810000_P01_INTERIOR_CAD (Autodesk Fusion 360 design; units mm, degrees)
description: INTERIOR | Nội thất | HS | P01
part number: 810000
description: INTERIOR - WORK WALL LEDGE ASSY | Bàn tựa vách làm việc (cụm) | HS | P01
part number: 810101
description: INTERIOR - LIGHT SHELF ASSY | Kệ đèn hắt (cụm) | HS | P01
part number: 810201
description: INTERIOR - LIGHT SHELF - BACK | Kệ đèn - vách sau | MP | P01
part number: 811201
description: INTERIOR - LIGHT SHELF - SIDE LH | Kệ đèn - vách trái | MP | P01
part number: 811202
description: INTERIOR - LIGHT SHELF - SIDE RH | Kệ đèn - vách phải | MP | P01
part number: 811203
description: ELECTRICAL - LED PROFILE - LIGHT SHELF - SURFACE 23 X 12.5 | Điện - thanh nhôm LED nổi 23 x 12.5 - kệ đèn | HOLD | P01
part number: 718101
description: INTERIOR - LEDGE - TOP | Mặt bàn tựa nhôm gấp 1.5 | MP | P01
part number: 811101
description: INTERIOR - LEDGE BRACKET - HOLD | Ke đỡ bàn tựa (chờ) | HOLD | P01
part number: 818101
description: INTERIOR - SCREEN RAIL - HOLD | Thanh treo màn hình (chờ) | HOLD | P01
part number: 818102
Autodesk Fusion 360 part; units mm, degrees
sketch "SECTION - LIGHT SHELF BACK" plane through (0, 0, 0) normal (1, 0, 0) x (0, 0, -1) in component "811201 INTERIOR - LIGHT SHELF - BACK"
  line L0 (-2230, 766) -> (-2230, 706)
  line L1 (-2230, 706) -> (-2250, 706)
  line L2 (-2250, 706) -> (-2250, 707)
  line L3 (-2250, 707) -> (-2231, 707)
  line L4 (-2231, 707) -> (-2231, 765)
  line L5 (-2231, 765) -> (-2270, 765)
  line L6 (-2270, 765) -> (-2270, 766)
  line L7 (-2270, 766) -> (-2230, 766)
  dimension "d965" = 2230
  dimension "d966" = 2250
  dimension "d967" = 2231
  dimension "d968" = 2270
  dimension "d969" = 706
  dimension "d970" = 707
  dimension "d971" = 765
  dimension "d972" = 766
  constraint vertical L0
  constraint vertical L2
  constraint vertical L4
  constraint vertical L6
  constraint horizontal L1
  constraint horizontal L3
  constraint horizontal L5
  constraint horizontal L7
  measures "d965" horizontal distance of origin L0.start
  measures "d966" horizontal distance of origin L1.end
  measures "d967" horizontal distance of origin L3.end
  measures "d968" horizontal distance of origin L5.end
  measures "d969" vertical distance of origin L0.end
  measures "d970" vertical distance of origin L2.end
  measures "d971" vertical distance of origin L4.end
  measures "d972" vertical distance of origin L6.end
extrude "EXTRUDE - LIGHT SHELF BACK" add sketch "SECTION - LIGHT SHELF BACK" along normal blind 2332 from surface at -1166 makes body 1 in component "811201 INTERIOR - LIGHT SHELF - BACK"
fillet "BEND INSIDE R (sh_r) - LIGHT SHELF BACK" radius 1 2 edges at (0, 765, 2231) (0, 707, 2231) on bodies 1 in component "811201 INTERIOR - LIGHT SHELF - BACK"
fillet "BEND OUTSIDE R (sh_r + sh_t) - LIGHT SHELF BACK" radius 2 2 edges at (0, 766, 2230) (0, 706, 2230) on bodies 1 in component "811201 INTERIOR - LIGHT SHELF - BACK"
sketch "SECTION - LIGHT SHELF LH" plane through (0, 0, 0) normal (0, 1, 0) x (1, 0, 0) in component "811202 INTERIOR - LIGHT SHELF - SIDE LH"
  line L0 (-1166, -2230) -> (-1106, -2230)
  line L1 (-1106, -2230) -> (-1106, -2250)
  line L2 (-1106, -2250) -> (-1107, -2250)
  line L3 (-1107, -2250) -> (-1107, -2231)
  line L4 (-1107, -2231) -> (-1165, -2231)
  line L5 (-1165, -2231) -> (-1165, -2270)
  line L6 (-1165, -2270) -> (-1166, -2270)
  line L7 (-1166, -2270) -> (-1166, -2230)
  dimension "d980" = 1106
  dimension "d981" = 1107
  dimension "d982" = 1165
  dimension "d983" = 1166
  dimension "d984" = 2230
  dimension "d985" = 2250
  dimension "d986" = 2231
  dimension "d987" = 2270
  constraint vertical L1
  constraint vertical L3
  constraint vertical L5
  constraint vertical L7
  constraint horizontal L0
  constraint horizontal L2
  constraint horizontal L4
  constraint horizontal L6
  measures "d980" horizontal distance of origin L0.end
  measures "d981" horizontal distance of origin L2.end
  measures "d982" horizontal distance of origin L4.end
  measures "d983" horizontal distance of origin L6.end
  measures "d984" vertical distance of origin L0.start
  measures "d985" vertical distance of origin L1.end
  measures "d986" vertical distance of origin L3.end
  measures "d987" vertical distance of origin L5.end
extrude "EXTRUDE - LIGHT SHELF LH" add sketch "SECTION - LIGHT SHELF LH" along normal blind 991 from surface at -285 separate body makes body 2 in component "811202 INTERIOR - LIGHT SHELF - SIDE LH"
fillet "BEND INSIDE R (sh_r) - LIGHT SHELF LH" radius 1 2 edges at (-1165, 210.5, 2231) (-1107, 210.5, 2231) on bodies 2 in component "811202 INTERIOR - LIGHT SHELF - SIDE LH"
fillet "BEND OUTSIDE R (sh_r + sh_t) - LIGHT SHELF LH" radius 2 2 edges at (-1166, 210.5, 2230) (-1106, 210.5, 2230) on bodies 2 in component "811202 INTERIOR - LIGHT SHELF - SIDE LH"
sketch "SECTION - LIGHT SHELF RH" plane through (0, 0, 0) normal (0, 1, 0) x (1, 0, 0) in component "811203 INTERIOR - LIGHT SHELF - SIDE RH"
  line L0 (1166, -2230) -> (1106, -2230)
  line L1 (1106, -2230) -> (1106, -2250)
  line L2 (1106, -2250) -> (1107, -2250)
  line L3 (1107, -2250) -> (1107, -2231)
  line L4 (1107, -2231) -> (1165, -2231)
  line L5 (1165, -2231) -> (1165, -2270)
  line L6 (1165, -2270) -> (1166, -2270)
  line L7 (1166, -2270) -> (1166, -2230)
  dimension "d995" = 1106
  dimension "d996" = 1107
  dimension "d997" = 1165
  dimension "d998" = 1166
  dimension "d999" = 2230
  dimension "d1000" = 2250
  dimension "d1001" = 2231
  dimension "d1002" = 2270
  constraint vertical L1
  constraint vertical L3
  constraint vertical L5
  constraint vertical L7
  constraint horizontal L0
  constraint horizontal L2
  constraint horizontal L4
  constraint horizontal L6
  measures "d995" horizontal distance of origin L0.end
  measures "d996" horizontal distance of origin L2.end
  measures "d997" horizontal distance of origin L4.end
  measures "d998" horizontal distance of origin L6.end
  measures "d999" vertical distance of origin L0.start
  measures "d1000" vertical distance of origin L1.end
  measures "d1001" vertical distance of origin L3.end
  measures "d1002" vertical distance of origin L5.end
extrude "EXTRUDE - LIGHT SHELF RH" add sketch "SECTION - LIGHT SHELF RH" along normal blind 991 from surface at -285 separate body makes body 3 in component "811203 INTERIOR - LIGHT SHELF - SIDE RH"
fillet "BEND INSIDE R (sh_r) - LIGHT SHELF RH" radius 1 2 edges at (1165, 210.5, 2231) (1107, 210.5, 2231) on bodies 3 in component "811203 INTERIOR - LIGHT SHELF - SIDE RH"
fillet "BEND OUTSIDE R (sh_r + sh_t) - LIGHT SHELF RH" radius 2 2 edges at (1166, 210.5, 2230) (1106, 210.5, 2230) on bodies 3 in component "811203 INTERIOR - LIGHT SHELF - SIDE RH"
ref_plane "WorkPlane1" through (0, 0, 2217.5) normal (0, 0, 1) x (1, 0, 0) in component "718101 ELECTRICAL - LED PROFILE - LIGHT SHELF - SURFACE 23 X 12.5"
sketch "OUTLINE - LED PROFILE RH" plane through (0, 0, 2217.5) normal (0, 0, 1) x (1, 0, 0) in component "718101 ELECTRICAL - LED PROFILE - LIGHT SHELF - SURFACE 23 X 12.5"
  line L0 (1128, -285) -> (1151, -285)
  line L1 (1151, -285) -> (1151, 706)
  line L2 (1151, 706) -> (1128, 706)
  line L3 (1128, 706) -> (1128, -285)
  dimension "d1012" = 23
  dimension "d1013" = 991
  dimension "d1014" = 1128
  dimension "d1015" = 285
  constraint horizontal L0
  constraint vertical L1
  constraint horizontal L2
  constraint vertical L3
  measures "d1012" horizontal distance of L0.start L0.end
  measures "d1013" vertical distance of L0.start L2.end
  measures "d1014" horizontal distance of origin L0.start
  measures "d1015" vertical distance of origin L0.start
extrude "EXTRUDE - LED PROFILE RH" add sketch "OUTLINE - LED PROFILE RH" along normal blind 12.5 separate body makes body 4 in component "718101 ELECTRICAL - LED PROFILE - LIGHT SHELF - SURFACE 23 X 12.5"
sketch "SECTION - LEDGE TOP" plane through (0, 0, 0) normal (0, 1, 0) x (1, 0, 0) in component "811101 INTERIOR - LEDGE - TOP"
  line L0 (911, -1067) -> (1161, -1067)
  line L1 (1161, -1067) -> (1161, -1042)
  line L2 (1161, -1042) -> (1159.5, -1042)
  line L3 (1159.5, -1042) -> (1159.5, -1065.5)
  line L4 (1159.5, -1065.5) -> (912.5, -1065.5)
  line L5 (912.5, -1065.5) -> (912.5, -1042)
  line L6 (912.5, -1042) -> (911, -1042)
  line L7 (911, -1042) -> (911, -1067)
  dimension "d1018" = 1161
  dimension "d1019" = 1159.5
  dimension "d1020" = 912.5
  dimension "d1021" = 911
  dimension "d1022" = 1067
  dimension "d1023" = 1042
  dimension "d1024" = 1065.5
  dimension "d1025" = 1042
  constraint vertical L1
  constraint vertical L3
  constraint vertical L5
  constraint vertical L7
  constraint horizontal L0
  constraint horizontal L2
  constraint horizontal L4
  constraint horizontal L6
  measures "d1018" horizontal distance of origin L0.end
  measures "d1019" horizontal distance of origin L2.end
  measures "d1020" horizontal distance of origin L4.end
  measures "d1021" horizontal distance of origin L6.end
  measures "d1022" vertical distance of origin L0.start
  measures "d1023" vertical distance of origin L1.end
  measures "d1024" vertical distance of origin L3.end
  measures "d1025" vertical distance of origin L5.end
extrude "EXTRUDE - LEDGE TOP" add sketch "SECTION - LEDGE TOP" along normal blind 1000 from surface at -259.5 separate body makes body 5 in component "811101 INTERIOR - LEDGE - TOP"
fillet "BEND INSIDE R (lg_r) - LEDGE TOP" radius 1.5 2 edges at (912.5, 240.5, 1065.5) (1159.5, 240.5, 1065.5) on bodies 5 in component "811101 INTERIOR - LEDGE - TOP"
fillet "BEND OUTSIDE R (lg_r + lg_t) - LEDGE TOP" radius 3 2 edges at (911, 240.5, 1067) (1161, 240.5, 1067) on bodies 5 in component "811101 INTERIOR - LEDGE - TOP"
sketch "SECTION - LEDGE BRACKET 1" plane through (0, 0, 0) normal (0, 1, 0) x (1, 0, 0) in component "818101 INTERIOR - LEDGE BRACKET - HOLD"
  line L0 (961, -915.5) -> (1159.5, -915.5)
  line L1 (1159.5, -915.5) -> (1159.5, -1062.5)
  line L2 (1159.5, -1062.5) -> (1156.5, -1065.5)
  line L3 (1156.5, -1065.5) -> (961, -1065.5)
  line L4 (961, -1065.5) -> (961, -915.5)
  dimension "d1033" = 1159.5
  dimension "d1034" = 1156.5
  dimension "d1035" = 961
  dimension "d1036" = 915.5
  dimension "d1037" = 1062.5
  dimension "d1038" = 1065.5
  constraint vertical L1
  constraint vertical L4
  constraint horizontal L0
  constraint horizontal L3
  measures "d1033" horizontal distance of origin L0.end
  measures "d1034" horizontal distance of origin L2.end
  measures "d1035" horizontal distance of origin L3.end
  measures "d1036" vertical distance of origin L0.start
  measures "d1037" vertical distance of origin L1.end
  measures "d1038" vertical distance of origin L2.end
extrude "EXTRUDE - LEDGE BRACKET 1" add sketch "SECTION - LEDGE BRACKET 1" along normal blind 30 from surface at 83.63 separate body makes body 6 in component "818101 INTERIOR - LEDGE BRACKET - HOLD"
sketch "SECTION - LEDGE BRACKET 2" plane through (0, 0, 0) normal (0, 1, 0) x (1, 0, 0) in component "818101 INTERIOR - LEDGE BRACKET - HOLD"
  line L0 (961, -915.5) -> (1159.5, -915.5)
  line L1 (1159.5, -915.5) -> (1159.5, -1062.5)
  line L2 (1159.5, -1062.5) -> (1156.5, -1065.5)
  line L3 (1156.5, -1065.5) -> (961, -1065.5)
  line L4 (961, -1065.5) -> (961, -915.5)
  dimension "d1042" = 1159.5
  dimension "d1043" = 1156.5
  dimension "d1044" = 961
  dimension "d1045" = 915.5
  dimension "d1046" = 1062.5
  dimension "d1047" = 1065.5
  constraint vertical L1
  constraint vertical L4
  constraint horizontal L0
  constraint horizontal L3
  measures "d1042" horizontal distance of origin L0.end
  measures "d1043" horizontal distance of origin L2.end
  measures "d1044" horizontal distance of origin L3.end
  measures "d1045" vertical distance of origin L0.start
  measures "d1046" vertical distance of origin L1.end
  measures "d1047" vertical distance of origin L2.end
extrude "EXTRUDE - LEDGE BRACKET 2" add sketch "SECTION - LEDGE BRACKET 2" along normal blind 30 from surface at 449.32 separate body makes body 7 in component "818101 INTERIOR - LEDGE BRACKET - HOLD"
ref_plane "WorkPlane1" through (0, 0, 1275) normal (0, 0, 1) x (1, 0, 0) in component "818102 INTERIOR - SCREEN RAIL - HOLD"
sketch "OUTLINE - SCREEN RAIL" plane through (0, 0, 1275) normal (0, 0, 1) x (1, 0, 0) in component "818102 INTERIOR - SCREEN RAIL - HOLD"
  line L0 (1136, -209.5) -> (1161, -209.5)
  line L1 (1161, -209.5) -> (1161, 690.5)
  line L2 (1161, 690.5) -> (1136, 690.5)
  line L3 (1136, 690.5) -> (1136, -209.5)
  dimension "d1053" = 25
  dimension "d1054" = 900
  dimension "d1055" = 1136
  dimension "d1056" = 209.5
  constraint horizontal L0
  constraint vertical L1
  constraint horizontal L2
  constraint vertical L3
  measures "d1053" horizontal distance of L0.start L0.end
  measures "d1054" vertical distance of L0.start L2.end
  measures "d1055" horizontal distance of origin L0.start
  measures "d1056" vertical distance of origin L0.start
extrude "EXTRUDE - SCREEN RAIL" add sketch "OUTLINE - SCREEN RAIL" along normal blind 50 separate body makes body 8 in component "818102 INTERIOR - SCREEN RAIL - HOLD"
ref_plane "WorkPlane1" through (0, 766, 0) normal (0, 1, 0) x (0, 0, 1) in component "811201 INTERIOR - LIGHT SHELF - BACK"
sketch "HOLE - LIGHT SHELF BACK CABLE HOLE 1" plane through (0, 766, 0) normal (0, 1, 0) x (1, 0, 0) in component "811201 INTERIOR - LIGHT SHELF - BACK"
  circle A0 centre (355, -2250) radius 5
  dimension "d1061" = 10
  dimension "d1062" = 355
  dimension "d1063" = 2250
  measures "d1061" diameter of A0
  measures "d1062" horizontal distance of origin A0.centre
  measures "d1063" vertical distance of origin A0.centre
extrude "CUT - LIGHT SHELF BACK CABLE HOLE 1" cut sketch "HOLE - LIGHT SHELF BACK CABLE HOLE 1" against normal blind 2 bodies 1 in component "811201 INTERIOR - LIGHT SHELF - BACK"
ref_plane "WorkPlane1" through (1166, 0, 0) normal (1, 0, 0) x (0, 1, 0) in component "811203 INTERIOR - LIGHT SHELF - SIDE RH"
sketch "HOLE - LIGHT SHELF RH CABLE HOLE 2" plane through (1166, 0, 0) normal (1, 0, 0) x (0, 0, -1) in component "811203 INTERIOR - LIGHT SHELF - SIDE RH"
  circle A0 centre (-2250, -209.5) radius 5
  dimension "d1068" = 10
  dimension "d1069" = 209.5
  dimension "d1070" = 2250
  measures "d1068" diameter of A0
  measures "d1069" vertical distance of origin A0.centre
  measures "d1070" horizontal distance of origin A0.centre
extrude "CUT - LIGHT SHELF RH CABLE HOLE 2" cut sketch "HOLE - LIGHT SHELF RH CABLE HOLE 2" against normal blind 2 bodies 3 in component "811203 INTERIOR - LIGHT SHELF - SIDE RH"
component "810101 INTERIOR - WORK WALL LEDGE ASSY" placed x (1, 0, 0) y (0, 1, 0) z (0, 0, 1) at (0, 0, 0)
component "810201 INTERIOR - LIGHT SHELF ASSY" placed x (1, 0, 0) y (0, 1, 0) z (0, 0, 1) at (0, 0, 0)
component "818102 INTERIOR - SCREEN RAIL - HOLD" placed x (1, 0, 0) y (0, 1, 0) z (0, 0, 1) at (0, 0, 0)
component "811101 INTERIOR - LEDGE - TOP" placed x (1, 0, 0) y (0, 1, 0) z (0, 0, 1) at (0, 0, 0) in component "810101 INTERIOR - WORK WALL LEDGE ASSY"
component "818101 INTERIOR - LEDGE BRACKET - HOLD" placed x (1, 0, 0) y (0, 1, 0) z (0, 0, 1) at (0, 0, 0) in component "810101 INTERIOR - WORK WALL LEDGE ASSY"
component "811201 INTERIOR - LIGHT SHELF - BACK" placed x (1, 0, 0) y (0, 1, 0) z (0, 0, 1) at (0, 0, 0) in component "810201 INTERIOR - LIGHT SHELF ASSY"
component "811202 INTERIOR - LIGHT SHELF - SIDE LH" placed x (1, 0, 0) y (0, 1, 0) z (0, 0, 1) at (0, 0, 0) in component "810201 INTERIOR - LIGHT SHELF ASSY"
component "811203 INTERIOR - LIGHT SHELF - SIDE RH" placed x (1, 0, 0) y (0, 1, 0) z (0, 0, 1) at (0, 0, 0) in component "810201 INTERIOR - LIGHT SHELF ASSY"
component "718101 ELECTRICAL - LED PROFILE - LIGHT SHELF - SURFACE 23 X 12.5" placed x (1, 0, 0) y (0, 1, 0) z (0, 0, 1) at (0, 0, 0) in component "810201 INTERIOR - LIGHT SHELF ASSY"
equation "pod_w = 2500 mm" comment "DECIDED: skeleton P04: D-01; conventions s4 (X = +-1250)"
equation "pod_d = 1700 mm" comment "DECIDED: skeleton P04: D-01; conventions s4 (Y = +-850)"
equation "pod_h = 2400 mm" comment "DECIDED: skeleton P04: D-21 (room floor to roof skin top)"
equation "glide_h = 10 mm" comment "ASSUMPTION: skeleton P04: layout study inputs.py glide_h"
equation "band_h = 100 mm" comment "SOURCE: skeleton P04: layout study B1 list B-BAND 100x40; inputs.py base_h"
equation "band_t = 40 mm" comment "SOURCE: skeleton P04: layout study B1 list B-BAND 100x40"
equation "skin_t = 3 mm" comment "DECIDED: skeleton P04: ACP skin, walls and ceiling (D-16; PM ruling 2026-10-31 on outer_t)"
equation "bond_t = 3 mm" comment "DECIDED: skeleton P04: bond line between the ACP and the frame (PM ruling 2026-10-31 on outer_t)"
equation "frame_t = 40 mm" comment "DECIDED: skeleton P04: aluminium frame tube depth, walls and ceiling (PM ruling 2026-10-31 on outer_t)"
equation "outer_t = skin_t + bond_t + frame_t" comment "DECIDED: skeleton P04: PM ruling 2026-10-31: ACP 3 + bond line 3 + frame 40, walls and ceiling (was 43)"
equation "cav_gap = 4 mm" comment "DECIDED: skeleton P04: D-16, D-42: the gap between the outer panel and the lining cassette in the wall and ceiling stack"
equation "cass_t = 34 mm" comment "SOURCE: skeleton P04: layout study B1 final list L-CASS 34 (tray + 25 gap + felt 9)"
equation "stack_t = outer_t + cav_gap + cass_t" comment "CALCULATION: skeleton P04: D-16, D-42 stack, walls and ceiling: outer panel + cavity gap + cassette (PM ruling 2026-10-31 on outer_t)"
equation "wall_depth = 1495 mm" comment "DECIDED: skeleton P04: PM ruling pass C: side walls start at the decor back plate (Y -645), as v1 (1496)"
equation "lin_gap = 4 mm" comment "ASSUMPTION: skeleton P04: PM ruling pass C: gap above the upper side linings so they stay floating (= the 4 mm stack gap)"
equation "seam_gap = 2.26 mm" comment "DECIDED: skeleton P04: PM ruling 2026-10-31 (Mechanical Checker F-001, F-005): the Joints Engineer's 2.26 mm at all nine site seam types, set by a metal stop (1.5 stop washer + 0.76 rivnut head; joints register section 2.8)"
equation "mat_t = 3 mm" comment "DECIDED: skeleton P04: D-72, PM ruling 2026-10-31 (from BASE): the 3 mm floor mat under the floor ply"
equation "floor_t = 9 mm" comment "DECIDED: skeleton P04: PM ruling 2026-10-31: 9 mm floor panels (was 15, layout study B1 list), on the mat"
equation "thresh_h = 13 mm" comment "DECIDED: skeleton P04: PM ruling 2026-10-31: 13 mm, a US-accessible threshold (D-18 had 20); the kick strip keeps its kick_gap above it"
equation "thresh_d = 60 mm" comment "SOURCE: skeleton P04: layout study B1 list B-THRESH 1176 x 60 x 20"
equation "decor_d = 205 mm" comment "SOURCE: skeleton P04: v1 geometry per the PM ruling on D-39 (as v1; the drawings win): v1 decor-frame drawing frames 191 (left) and 197 (right) deep plus ACP and back plate = the v1 STEP shell, Y -850 to -645 = 205. D-39 and the B1 list say 230-235 (v1 BOM); see BUILD-RECORD-P02"
equation "dl_w = 278 mm" comment "SOURCE: skeleton P04: B1 list F-DL 278 (v1 BOM DL)"
equation "dr_w = 1016 mm" comment "SOURCE: skeleton P04: B1 list F-DR 1016 (v1 STEP solid 78)"
equation "dt_w = 1697 mm" comment "SOURCE: skeleton P04: B1 list F-DT 1697 (v1 BOM DT)"
equation "dt_h = 280 mm" comment "SOURCE: skeleton P04: B1 list F-DT 280"
equation "door_w = 1176 mm" comment "DECIDED: skeleton P04: D-46"
equation "door_h = 2011 mm" comment "SOURCE: skeleton P04: B1 list F-GLASS-DOOR 2011; v1 STEP solid 238"
equation "glass_t = 8.76 mm" comment "DECIDED: skeleton P04: D-46 (4+4 laminate)"
equation "glass_y = 699 mm" comment "SOURCE: skeleton P04: v1 STEP solid 238 centre Y = -699 (layout study data)"
equation "kick_d = 20 mm" comment "ASSUMPTION: skeleton P04: kick strip envelope depth (D-40 gives the height only)"
equation "kick_gap = 7 mm" comment "SOURCE: skeleton P04: FRONT door unit: 7 mm running gap between the threshold and the kick strip for the drop seal (Mechanical Checker F-002 on P03)"
equation "fr_dz = 17 mm" comment "CALCULATION: skeleton P04: v1 front top 2417 (v2 frame) - pod_h 2400"
equation "door_xl = 289 mm" comment "SOURCE: skeleton P04: V1-FRONT-FACETS: door left edge X -961 = -1250 + 289"
equation "door_xbr = 1464 mm" comment "SOURCE: skeleton P04: V1-FRONT-FACETS: door bottom-right X 214"
equation "door_xtr = 1182 mm" comment "SOURCE: skeleton P04: V1-FRONT-FACETS: door top-right X -68"
equation "door_zb = 122 mm - fr_dz" comment "SOURCE: skeleton P04: V1-FRONT-FACETS: door bottom Z 122"
equation "door_zt = 2133 mm - fr_dz" comment "SOURCE: skeleton P04: V1-FRONT-FACETS: door top Z 2133"
equation "glass_gap = 4 mm" comment "DECIDED: skeleton P04: PM ruling 2026-10-31 on Mechanical Checker F-014: the fixed glass's free edge runs parallel to the door's slanted edge, 4.0 mm away (FRONT's glass in PR #28 is the reference)"
equation "fix_xbr = 302 mm" comment "SOURCE: skeleton P04: V1-FRONT-FACETS: fixed glass bottom-right X 948 = 1250 - 302"
equation "fix_xk = 501 mm" comment "SOURCE: skeleton P04: V1-FRONT-FACETS: fixed glass knee X 749 = 1250 - 501"
equation "fix_zk = 1538 mm - fr_dz" comment "SOURCE: skeleton P04: V1-FRONT-FACETS: fixed glass knee Z 1538"
equation "fix_xtr = 1480 mm" comment "SOURCE: skeleton P04: V1-FRONT-FACETS: fixed glass top-right X 230 = -1250 + 1480"
equation "fix_zb = 119 mm - fr_dz" comment "SOURCE: skeleton P04: V1-FRONT-FACETS: fixed glass bottom Z 119"
equation "fix_zt = 2136 mm - fr_dz" comment "SOURCE: skeleton P04: V1-FRONT-FACETS: fixed glass top Z 2136"
equation "dt_zb = 2137 mm - fr_dz" comment "SOURCE: skeleton P04: V1-FRONT-FACETS: DT and DR edge above the glass Z 2137"
equation "ch_zlo = 2217 mm - fr_dz" comment "SOURCE: skeleton P04: V1-FRONT-FACETS: top chamfer front edge Z 2217 at Y -848"
equation "ch_yb = 672 mm" comment "SOURCE: skeleton P04: V1-FRONT-FACETS: top chamfer back edge Y -672"
equation "dl_x2 = 92 mm" comment "SOURCE: skeleton P04: V1-FRONT-FACETS: DL facet knee X -1158 = -1250 + 92"
equation "dl_y2 = 752 mm" comment "SOURCE: skeleton P04: V1-FRONT-FACETS: DL facet knee Y -752"
equation "dl_x3 = 271 mm" comment "SOURCE: skeleton P04: V1-FRONT-FACETS: DL front corner X -979"
equation "dl_y3 = 844 mm" comment "SOURCE: skeleton P04: V1-FRONT-FACETS: DL front corner Y -844"
equation "dl_y1 = 670 mm" comment "SOURCE: skeleton P04: V1-FRONT-FACETS: DL outer facet start Y -670"
equation "dl_zo = 2414 mm - fr_dz" comment "SOURCE: skeleton P04: V1-FRONT-FACETS: DL top at the outer corner Z 2414"
equation "dt_x2 = 281 mm" comment "SOURCE: skeleton P04: V1-FRONT-FACETS: DT lower facet left X -969 = -1250 + 281"
equation "dt_y2 = 767 mm" comment "SOURCE: skeleton P04: V1-FRONT-FACETS: DT lower facet left Y -767"
equation "dt_y3 = 753 mm" comment "SOURCE: skeleton P04: V1-FRONT-FACETS: DT lower facet outer Y -753 at X -1154"
equation "dr_xc = 198 mm" comment "SOURCE: skeleton P04: V1-FRONT-FACETS: DR corner facet front X 1052 = 1250 - 198"
equation "dt_xr = 1699 mm" comment "SOURCE: skeleton P04: V1-FRONT-FACETS: DT/DR joint at the top, X 449 = -1250 + 1699 (PM ruling pass C)"
equation "dr_yc = 672 mm" comment "SOURCE: skeleton P04: V1-FRONT-FACETS: DR corner facet back Y -672"
equation "fix_xbl = door_xbr + ( door_zb - fix_zb ) * ( door_xbr - door_xtr ) / ( door_zt - door_zb ) + glass_gap * sqrt(( door_xbr - door_xtr ) * ( door_xbr - door_xtr ) + ( door_zt - door_zb ) * ( door_zt - door_zb )) / ( door_zt - door_zb )" comment "CALCULATION: skeleton P04: F-014: fixed glass bottom-left, on the line glass_gap from the door's slanted edge (was v1's 1468)"
equation "fix_xtl = door_xbr + ( door_zb - fix_zt ) * ( door_xbr - door_xtr ) / ( door_zt - door_zb ) + glass_gap * sqrt(( door_xbr - door_xtr ) * ( door_xbr - door_xtr ) + ( door_zt - door_zb ) * ( door_zt - door_zb )) / ( door_zt - door_zb )" comment "CALCULATION: skeleton P04: F-014: fixed glass top-left, on the same line (was v1's 1184)"
equation "floor_top = mat_t + floor_t" comment "CALCULATION: skeleton P04: D-72: the floor top, Z 12 (mat 3 + ply 9); the threshold stands thresh_h above the room floor"
equation "wall_z0 = glide_h + band_h" comment "CALCULATION: skeleton P04: base band top: glides + band"
equation "panel_z0 = wall_z0 + seam_gap" comment "CALCULATION: skeleton P04: walls stand one seam_gap above the band top (joints register 2.8, IF-01)"
equation "wall_h = pod_h - wall_z0" comment "CALCULATION: skeleton P04: 2290 = layout study v2_model wall_h"
equation "side_h = ( wall_h - 2 * seam_gap ) / 2" comment "CALCULATION: skeleton P04: D-23: 2 sheets per side wall; the gap on the band and the horizontal seam (joints register 2.8)"
equation "side_l = wall_depth - seam_gap" comment "CALCULATION: skeleton P04: side panel length along Y: the seam_gap at the decor's back plate (joints register 2.8, IF-07)"
equation "back_oh = pod_h - outer_t - seam_gap - panel_z0" comment "CALCULATION: skeleton P04: PM ruling 2026-10-31 (pass D, F-004): the back outer frames run up to the ceiling frame (pod_h - outer_t), less the seam_gap under it, closing the slot at the back top edge"
equation "back_ph = ( back_oh - seam_gap ) / 2" comment "CALCULATION: skeleton P04: D-23: 4 sheets on the back, two equal rows with one seam_gap between them (joints register 2.8); the lower back linings match the lower row, as on the side walls"
equation "half_pw = ( pod_w - 2 * outer_t - 3 * seam_gap ) / 2" comment "CALCULATION: skeleton P04: SKIN width of each back and ceiling panel: two skins and three seam_gap seams between the side frames (F-001, joints register 2.8)"
equation "close_gap = 5.5 mm" comment "DECIDED: skeleton P04: PM ruling 2026-10-31 (joints register, F-011/F-012): frame gap at the closing seams B1-B2, B3-B4 and C1-C2, which have no hard stop (slotted holes, thicker gasket)"
equation "half_fw = ( pod_w - 2 * outer_t - 2 * seam_gap - close_gap ) / 2" comment "CALCULATION: skeleton P04: FRAME width of each back and ceiling panel: the skins overhang their frames by half_pw - half_fw at the closing seam (PM ruling 2026-10-31)"
equation "inner_w = pod_w - 2 * stack_t" comment "CALCULATION: skeleton P04: inside width between the side linings"
equation "bolt_edge_inset = 220 mm" comment "DECIDED: skeleton P04: PM ruling 2026-10-31: on every bolted edge the end bolts sit this far in from each panel end (the FRAME end, where the bolts go), the rest evenly spaced"
equation "spigot_inset = 100 mm" comment "DECIDED: skeleton P04: PM ruling 2026-10-31: locating spigots this far in from each panel end (round hole at one end, slot at the other)"
equation "base_bolt_edge = bolt_edge_inset" comment "DECIDED: skeleton P04: J-BASE-01 wall to band: the edge rule (kept by this name for parts already linked)"
equation "n_base_bolt = 4" comment "DECIDED: skeleton P04: PM ruling 2026-10-31, J-BASE-01: bolts per panel along the band, evenly spaced"
equation "base_spigot_inset = spigot_inset" comment "DECIDED: skeleton P04: J-BASE-01: the spigot rule (kept by this name for parts already linked)"
equation "base_side_y0 = pod_d / 2 - wall_depth + seam_gap" comment "CALCULATION: skeleton P04: J-BASE-01: side bolt lines start at the side panel's front end (first bolt base_bolt_edge further on)"
equation "side_base_pitch = ( side_l - 2 * base_bolt_edge ) / ( n_base_bolt - 1 )" comment "CALCULATION: skeleton P04: J-BASE-01 bolt pitch along a side panel"
equation "base_back_x0 = pod_w / 2 - outer_t - seam_gap" comment "CALCULATION: skeleton P04: J-BASE-01: back bolt lines start at each back FRAME's outer end, X -/+ this (first bolt base_bolt_edge further in)"
equation "back_base_pitch = ( half_fw - 2 * base_bolt_edge ) / ( n_base_bolt - 1 )" comment "DECIDED: skeleton P04: PM ruling 2026-10-31 (Reviewer 5 P2 on #58): J-BASE-01 pitch along a back panel, measured on the FRAME (half_fw), where the bolts go; 'panel end' means the frame end"
equation "ceil_bolt_z = pod_h - outer_t + frame_t / 2" comment "DECIDED: skeleton P04: PM ruling 2026-10-31, J-CEIL-01 wall to ceiling: the bolt line on the ceiling frame's centre (Z 2374)"
equation "n_ceil_side_bolt = 4" comment "DECIDED: skeleton P04: PM ruling 2026-10-31, J-CEIL-01: bolts along each side wall top"
equation "n_ceil_back_bolt = 4" comment "DECIDED: skeleton P04: PM ruling 2026-10-31, J-CEIL-01: bolts along each back panel top, like the base (pitch about 253, every edge 350 or less; joints register: 82 bolts in all)"
equation "ceil_side_y0 = pod_d / 2 - wall_depth" comment "DECIDED: skeleton P04: PM ruling 2026-10-31 (joints register): J-CEIL-01 side bolt lines start at Y -645, measured along the ceiling (first bolt bolt_edge_inset further on)"
equation "ceil_side_pitch = ( wall_depth - 2 * bolt_edge_inset ) / ( n_ceil_side_bolt - 1 )" comment "DECIDED: skeleton P04: PM ruling 2026-10-31 (joints register): J-CEIL-01 pitch along a side wall top, over the ceiling's length (was over the side panel's)"
equation "ceil_back_x0 = pod_w / 2 - outer_t - seam_gap" comment "DECIDED: skeleton P04: PM ruling 2026-10-31 (joints register): J-CEIL-01 back bolt lines start at each back frame's outer end, X -/+ this"
equation "ceil_back_pitch = ( half_fw - 2 * bolt_edge_inset ) / ( n_ceil_back_bolt - 1 )" comment "DECIDED: skeleton P04: PM ruling 2026-10-31 (joints register): J-CEIL-01 pitch along a back panel top, on the frame (half_fw)"
equation "tube_w = 20 mm" comment "CONFIRMED: D-34, D-54: aluminium 20 x 40 x 1.2 members (the 20 mm face lies in the plane of the panel)"
equation "tube_t = 1.2 mm" comment "CONFIRMED: D-54: the frames stay 1.2 mm (rivnut grip check passed); D-85 keeps the ceiling's cross members at 1.2 too, since they carry the overhead clips and catches (T07, T08 test on 1.2)"
equation "back_w = 40 mm" comment "CONFIRMED: R-J3 (joints register 2.4): the ceiling's back member is 40 x 40, so the back panel's top tube overlaps it by 34 and its rivnuts sit on a 40 mm face"
equation "fr_n = 3" comment "CONFIRMED: PM ruling on the CEILING plan, 2026-10-31: 3 cross members between the side and seam members"
equation "fr_pitch = ( wall_depth - tube_w ) / ( fr_n + 1 )" comment "CALCULATION: centre spacing of the cross members, front member to back member: (1495 - 20) / 4 = 368.75, 400 or less (D-16)"
equation "hole_clr = 7 mm" comment "CONFIRMED: R-J6 (joints register 2.9): bolt clearance hole, positioned to +/-0.2 from the spigot hole"
equation "hole_acc = 19 mm" comment "CONFIRMED: joints register 2.2, 2.9: access hole, so the 18 mm head washer goes in with the bolt"
equation "hole_rvn = 9.53 mm" comment "SOURCE: H-03 Sherex CAH2-610-4.2 rivnut (steel, D-131): hole 9.53 +0.10, as the aluminium part's (joints register H-03, SHX)"
equation "spig_hole = 8.5 mm" comment "CONFIRMED: R-J13: spigot hole 8.5, round at one end of the edge, an 8.5 x 14 slot along it at the other"
equation "spig_slot = 14 mm" comment "CONFIRMED: R-J13: the spigot slot's length along the edge (+/-2.75 of travel for the 8 mm spigot)"
equation "lead_in = 1 mm" comment "CONFIRMED: R-J9 (joints register 2.10): 1 x 45 deg lead-in on the lower edges of the C1-C2 faces, so C2 drops past C1 without catching the seal"
equation "cj_back_y = pod_d / 2 - outer_t + frame_t / 2" comment "CONFIRMED: R-J15 (joints register 2.4): the back edges' bolt line on the back panel's top tube centre (Y +824)"
equation "cj_pin_n = 4" comment "CONFIRMED: J-CEIL-02 (joints register 3.6): 4 pins at the 220 mm rule along the C1-C2 seam"
equation "cj_pin_pitch = ( wall_depth - 2 * bolt_edge_inset ) / ( cj_pin_n - 1 )" comment "CALCULATION: J-CEIL-02 pins along the ceiling's 1495 from Y -645 + 220, as the side edges (joints register 2.9)"
equation "cj_spig_x0 = close_gap / 2 + spigot_inset" comment "CALCULATION: R-J13: spigots 100 in from each frame end. The round hole sits at the centre-seam end, since ST-04 runs from the round hole to the closing face (+/-0.1); the slot at the side end lets the side bolts pull C1 and C2 onto their stops"
equation "cj_spig_x1 = close_gap / 2 + half_fw - spigot_inset" comment "CALCULATION: R-J13: the slot 100 in from the frame's side end"
equation "x1_ov = 16 mm" comment "CONFIRMED: PM ruling 2026-11-01 (D-87 hooks): cross member X1 sits this far over the soffit's back edge, so the soffit's back hangers have a member above them; its back face stays over the cassette for the clips"
equation "hang_x = inner_w / 4" comment "CALCULATION: PM ruling 2026-11-01: soffit keyhole studs at the middle of each ceiling half's front member and X1 (clear of the clips, the catches and the roof slot)"
equation "lock_x = inner_w / 2 - 66 mm" comment "ASSUMPTION: PM ruling 2026-11-01: two captive screws (5 mm key) lock the soffit, so taking a cassette out can never free it; both in C1's front member over the soffit's left inlet plenum, where no cartridge is, reached through the left hinged underside (X -1100 and -950)"
equation "lock_dx = 150 mm" comment "ASSUMPTION: spacing of the two soffit lock screws along the front member"
equation "slot_x0 = 872 mm" comment "SOURCE: air report 7e (sized on skeleton P04): roof slot X 872 to 1157, over the soffit's exhaust fan box"
equation "slot_w = 285 mm" comment "SOURCE: air report 7e: roof slot 285 x 294"
equation "slot_d = 294 mm" comment "SOURCE: air report 7e: roof slot 285 x 294"
equation "slot_y0 = -620 mm" comment "CONFIRMED: D-61, PM ruling 2026-10-31: roof slot Y -620 to -326, 5 mm clear of the frame's front member"
equation "cs_front = 360 mm" comment "CONFIRMED: D-60 soffit over the door head, 360 deep and 220 tall (Z 2120 to 2340), flush with the air column's face (PM rulings 2026-10-31, air group); the cassettes stop at its back face (PM ruling 2026-10-31)"
equation "cs_gap = 3 mm" comment "ASSUMPTION: edge gap round the cassette to the next lining, the other cassette or the top decor block; the 3.2 mm PORON gasket (selection D) just touches across it"
equation "cs_w = inner_w / 2 - 2 * cs_gap" comment "CALCULATION: cassette width: half the 2338 inside width less a gap each side = 1163"
equation "cs_d = wall_depth - stack_t - cs_front - 2 * cs_gap" comment "CALCULATION: cassette length front to back: the 1414 envelope (decor back plate to the back lining face) less the soffit and a gap each end = 1408 with no soffit"
equation "tray_t = 0.5 mm" comment "CONFIRMED: D-37: galvanised steel tray 0.5 mm (DX51D+Z, selection B)"
equation "tray_h = cass_t" comment "CALCULATION: PM ruling on the CEILING plan, 2026-10-31: the returns run the full cassette depth (34) and turn in under the felt edge"
equation "lip_w = 12 mm" comment "CONFIRMED: PM ruling on the CEILING plan, 2026-10-31: a 12 mm lip under the felt edge"
equation "bend_r = tray_t" comment "ASSUMPTION: inside bend radius 1 x t for 0.5 mm DX51D (the sheet metal rule's bend radius is its Thickness); the factory's tooling sets it (guideline 9)"
equation "felt_t = 9 mm" comment "CONFIRMED: D-17: 9 mm PET felt on the cassette face (plan VT03-PET)"
equation "felt_c = 1 mm" comment "ASSUMPTION: felt edge clearance inside the returns, so the felt drops onto the lips"
equation "gap_h = tray_h - felt_t - 2 * tray_t" comment "CALCULATION: air gap between the tray base and the felt (24): the cable path (D-41) and the acoustic gap (D-17)"
equation "rib_n = 2" comment "CONFIRMED: PM ruling on the CEILING plan, 2026-10-31: 2 ribs keep the felt flat"
equation "rib_off = cs_w / 6" comment "CALCULATION: rib centre from the cassette centre line: with 2 ribs the felt spans 3 equal widths of cs_w / 3 = 388"
equation "rib_crown = 20 mm" comment "ASSUMPTION: flat width of the rib that carries the felt"
equation "rib_fl = 12 mm" comment "ASSUMPTION: rib top flange width against the tray base; the rib-to-tray joint is HOLD"
equation "rib_end = 5 mm" comment "ASSUMPTION: clearance from each rib end to the returns"
equation "fill_t = 40 mm" comment "CONFIRMED: D-24: 40 mm PET fill rides on the cassette back (25 kg/m3 by default, PM ruling 2026-10-31)"
equation "fill_c = 5 mm" comment "ASSUMPTION: fill clearance to the frame members, clips and catches, so the cassette never touches the frame (D-17)"
equation "fill_min = 100 mm" comment "ASSUMPTION: a fill strip shorter than this isn't made (a bay mostly over the soffit)"
equation "fill_hw = inner_w / 4 - close_gap / 2 - tube_w - fill_c" comment "CALCULATION: half length of a fill strip, set by the seam member over the cassette's inner edge and used on both sides, so both cassettes stay the same part"
equation "clip_w = 40 mm" comment "ASSUMPTION: clip space along X; HOLD H03 / ISS-076 until a clip is named with its rating"
equation "clip_d = 30 mm" comment "ASSUMPTION: clip space out from the member face; HOLD H03 / ISS-076"
equation "clip_h = 30 mm" comment "ASSUMPTION: clip space above the tray; HOLD H03 / ISS-076"
equation "catch_w = 40 mm" comment "ASSUMPTION: safety catch space along X; HOLD H04 / ISS-076"
equation "catch_d = 30 mm" comment "ASSUMPTION: safety catch space out from the member face; HOLD H04 / ISS-076"
equation "catch_h = 40 mm" comment "ASSUMPTION: safety catch space above the tray, up the member face; HOLD H04 / ISS-076"
equation "cable_hole = 19.1 mm" comment "CONFIRMED: PM ruling 2026-11-01: the panel hole ELECTRICAL's cable bushing needs, in the front and back returns: the voice cockpit route from the back wall to the front (REQ-VCK-03, D-41) and the spare path (ISS-069)"
equation "sprk_d = 150 mm" comment "ASSUMPTION: reserved round zone for a later sprinkler drop (REQ-US-01)"
equation "sh_d = 60 mm" comment "ASSUMPTION: D-70 (PM ruling 2026-10-31): slim light shelf; 60 out from the lining face"
equation "sh_hb = 40 mm" comment "ASSUMPTION: back flange height, screwed to the wall cassette"
equation "sh_hl = 20 mm" comment "ASSUMPTION: front lip height: hides the up-light strip from a seated eye"
equation "sh_t = 1 mm" comment "ASSUMPTION: D-85 budget 0.4 kg/m: 1.0 mm aluminium, 118 mm2 section (0.32 kg/m) plus the strip"
equation "sh_r = sh_t" comment "CONFIRMED: inside bend radius of the shelf's two folds: the Lead's ruling 2026-11-01 on #335 (the drawing generator's bent sheet mode): every fold's inside radius equals the sheet, a safe bend for this aluminium; the flats use K 0.44 (assumption until the factory's bend table sets it), and model, STEP and DXF must agree"
equation "sh_z0 = 2230 mm" comment "ASSUMPTION: shelf underside; ELECTRICAL's feed and call-light drop are at Z 2250, in the back flange, and the felt ceiling (Z 2316) is 46 above the flange"
equation "lp_x0 = 15 mm" comment "ASSUMPTION: D-126: the LED profile under the right run, 15 out from the lining (where the folded channel was)"
equation "lp_w = 23 mm" comment "SOURCE: D-126: surface LED profile of the Tech-Light P13-2 type (public catalogue): 23 wide outside"
equation "lp_h = 12.5 mm" comment "ASSUMPTION: D-126: the same profile, 12.5 deep with its clip-in cover; D-127 makes the cover satin in the same clip-in style, so the depth is taken as the same until the product is named"
equation "lp_in = 20 mm" comment "SOURCE: D-126: 20 inside at the strip base, two 8 mm strips side by side (the catalogue says so; ELECTRICAL needs 20 or more)"
equation "cab_d = 10 mm" comment "ASSUMPTION: cable hole in the back flange for the feed and the call-light drop"
equation "feed_x = 355 mm" comment "CONFIRMED: ELECTRICAL's input via the PM, 2026-11-01: the feed point at X 355 on the back wall, Z 2250"
equation "call_y = -209.5 mm" comment "CONFIRMED: ELECTRICAL's input via the PM, 2026-11-01: the call-light drop at Y -209.5 on the right wall, Z 2250"
equation "cab_z = 2250 mm" comment "CONFIRMED: ELECTRICAL's input via the PM, 2026-11-01: both at Z 2250"
equation "lg_l = 1000 mm" comment "CONFIRMED: D-70 (PM ruling 2026-10-31): a 1000 mm ledge on the work wall"
equation "lg_d = 250 mm" comment "ASSUMPTION: ledge depth: room for a keyboard, leaning on it standing"
equation "lg_z = 1067 mm" comment "ASSUMPTION: ledge top: standing lean height"
equation "lg_t = 1.5 mm" comment "CONFIRMED: D-85: 1.5 mm folded aluminium"
equation "lg_r = lg_t" comment "CONFIRMED: inside bend radius of the ledge's two folds: the Lead's ruling 2026-11-01 on #335 (the drawing generator's bent sheet mode): every fold's inside radius equals the sheet, a safe bend for this aluminium; the flats use K 0.44 (assumption until the factory's bend table sets it), and model, STEP and DXF must agree"
equation "lg_lip = 25 mm" comment "ASSUMPTION: front lip folded down"
equation "lg_up = 25 mm" comment "ASSUMPTION: back flange folded down, at the wall"
equation "lg_gap = 5 mm" comment "CALCULATION: the ledge, its brackets and the screen rail stand 5 off the lining's face, so nothing fixed to the frame touches the floating lining: D-17 (the cassette never touches the frame) and D-57's 4 mm (the wall stack's gap), plus 1 for the felt's thickness tolerance; the mechanical check's LINING-FLOATS rule found 2.0 to the lower side cassette's tray at the old 2"
equation "br_w = 200 mm" comment "ASSUMPTION: ledge bracket arm under the ledge, HOLD (a rated concealed shelf bracket)"
equation "br_h = 150 mm" comment "ASSUMPTION: ledge bracket height at the wall, HOLD"
equation "br_t = 30 mm" comment "ASSUMPTION: ledge bracket width along the wall, HOLD"
equation "br_rel = 2 * lg_t" comment "CALCULATION: each bracket envelope's top back edge cut 45 deg this far, so it clears the ledge's inside bend (radius lg_r) where the top meets the back flange: a real bracket needs the same relief"
equation "br_y1 = 98.63 mm" comment "SOURCE: WALL's right lower panel R1: mid stile at Y 98.63 (side panel stile pitch 365.69, mirror of L1)"
equation "br_y2 = 464.32 mm" comment "SOURCE: WALL's R1: mid stile at Y 464.32"
equation "sr_l = 900 mm" comment "CONFIRMED: D-70 (PM ruling 2026-10-31): a screen up to about 900 mm wide"
equation "sr_z = 1300 mm" comment "ASSUMPTION: rail centre height; the screen hangs on it above the ledge"
equation "sr_d = 25 mm" comment "ASSUMPTION: rail depth out from the lining, HOLD (a bought VESA rail)"
equation "sr_h = 50 mm" comment "ASSUMPTION: rail height, HOLD"
equation "d965 = abs(sh_z0)"
equation "d966 = abs(sh_z0 + sh_hl)"
equation "d967 = abs(sh_z0 + sh_t)"
equation "d968 = abs(sh_z0 + sh_hb)"
equation "d969 = abs(( ( pod_d / 2 - stack_t ) - ( sh_d ) ))"
equation "d970 = abs(( ( pod_d / 2 - stack_t ) - ( sh_d - sh_t ) ))"
equation "d971 = abs(( ( pod_d / 2 - stack_t ) - ( sh_t ) ))"
equation "d972 = abs(( ( pod_d / 2 - stack_t ) - ( 0 mm ) ))"
equation "d973 = ( ( -pod_w / 2 + stack_t ) ) * ( 1 )"
equation "d974 = ( ( pod_w / 2 - stack_t ) ) - ( ( -pod_w / 2 + stack_t ) )"
equation "d977 = sh_r"
equation "d979 = sh_r + sh_t"
equation "d980 = abs(( ( -pod_w / 2 + stack_t ) + ( sh_d ) ))"
equation "d981 = abs(( ( -pod_w / 2 + stack_t ) + ( sh_d - sh_t ) ))"
equation "d982 = abs(( ( -pod_w / 2 + stack_t ) + ( sh_t ) ))"
equation "d983 = abs(( ( -pod_w / 2 + stack_t ) + ( 0 mm ) ))"
equation "d984 = abs(sh_z0)"
equation "d985 = abs(sh_z0 + sh_hl)"
equation "d986 = abs(sh_z0 + sh_t)"
equation "d987 = abs(sh_z0 + sh_hb)"
equation "d988 = ( ( pod_d / 2 - wall_depth + cs_front ) ) * ( 1 )"
equation "d989 = ( ( pod_d / 2 - stack_t ) - sh_d ) - ( ( pod_d / 2 - wall_depth + cs_front ) )"
equation "d992 = sh_r"
equation "d994 = sh_r + sh_t"
equation "d995 = abs(( ( pod_w / 2 - stack_t ) - ( sh_d ) ))"
equation "d996 = abs(( ( pod_w / 2 - stack_t ) - ( sh_d - sh_t ) ))"
equation "d997 = abs(( ( pod_w / 2 - stack_t ) - ( sh_t ) ))"
equation "d998 = abs(( ( pod_w / 2 - stack_t ) - ( 0 mm ) ))"
equation "d999 = abs(sh_z0)"
equation "d1000 = abs(sh_z0 + sh_hl)"
equation "d1001 = abs(sh_z0 + sh_t)"
equation "d1002 = abs(sh_z0 + sh_hb)"
equation "d1003 = ( ( pod_d / 2 - wall_depth + cs_front ) ) * ( 1 )"
equation "d1004 = ( ( pod_d / 2 - stack_t ) - sh_d ) - ( ( pod_d / 2 - wall_depth + cs_front ) )"
equation "d1007 = sh_r"
equation "d1009 = sh_r + sh_t"
equation "d1010 = sh_z0 - lp_h"
equation "d1012 = ( ( pod_w / 2 - stack_t ) - lp_x0 ) - ( ( pod_w / 2 - stack_t ) - lp_x0 - lp_w )"
equation "d1013 = ( ( pod_d / 2 - stack_t ) - sh_d ) - ( ( pod_d / 2 - wall_depth + cs_front ) )"
equation "d1014 = abs(( pod_w / 2 - stack_t ) - lp_x0 - lp_w)"
equation "d1015 = abs(( pod_d / 2 - wall_depth + cs_front ))"
equation "d1016 = ( sh_z0 ) - ( sh_z0 - lp_h )"
equation "d1018 = abs(( ( pod_w / 2 - stack_t ) - lg_gap ))"
equation "d1019 = abs(( ( pod_w / 2 - stack_t ) - lg_gap ) - lg_t)"
equation "d1020 = abs(( ( pod_w / 2 - stack_t ) - lg_gap - lg_d ) + lg_t)"
equation "d1021 = abs(( ( pod_w / 2 - stack_t ) - lg_gap - lg_d ))"
equation "d1022 = abs(lg_z)"
equation "d1023 = abs(lg_z - lg_up)"
equation "d1024 = abs(lg_z - lg_t)"
equation "d1025 = abs(lg_z - lg_lip)"
equation "d1026 = ( ( ( pod_d / 2 - wall_depth + cs_front ) + ( ( pod_d / 2 - stack_t ) - ( pod_d / 2 - wall_depth + cs_front ) - lg_l ) / 2 ) ) * ( 1 )"
equation "d1027 = ( ( ( pod_d / 2 - wall_depth + cs_front ) + ( ( pod_d / 2 - stack_t ) - ( pod_d / 2 - wall_depth + cs_front ) - lg_l ) / 2 ) + lg_l ) - ( ( ( pod_d / 2 - wall_depth + cs_front ) + ( ( pod_d / 2 - stack_t ) - ( pod_d / 2 - wall_depth + cs_front ) - lg_l ) / 2 ) )"
equation "d1030 = lg_r"
equation "d1032 = lg_r + lg_t"
equation "d1033 = abs(( ( pod_w / 2 - stack_t ) - lg_gap - lg_t ))"
equation "d1034 = abs(( ( pod_w / 2 - stack_t ) - lg_gap - lg_t ) - br_rel)"
equation "d1035 = abs(( ( pod_w / 2 - stack_t ) - lg_gap - br_w ))"
equation "d1036 = abs(( ( lg_z - lg_t ) - br_h ))"
equation "d1037 = abs(( lg_z - lg_t ) - br_rel)"
equation "d1038 = abs(( lg_z - lg_t ))"
equation "d1039 = ( br_y1 - br_t / 2 ) * ( 1 )"
equation "d1040 = ( br_y1 + br_t / 2 ) - ( br_y1 - br_t / 2 )"
equation "d1042 = abs(( ( pod_w / 2 - stack_t ) - lg_gap - lg_t ))"
equation "d1043 = abs(( ( pod_w / 2 - stack_t ) - lg_gap - lg_t ) - br_rel)"
equation "d1044 = abs(( ( pod_w / 2 - stack_t ) - lg_gap - br_w ))"
equation "d1045 = abs(( ( lg_z - lg_t ) - br_h ))"
equation "d1046 = abs(( lg_z - lg_t ) - br_rel)"
equation "d1047 = abs(( lg_z - lg_t ))"
equation "d1048 = ( br_y2 - br_t / 2 ) * ( 1 )"
equation "d1049 = ( br_y2 + br_t / 2 ) - ( br_y2 - br_t / 2 )"
equation "d1051 = sr_z - sr_h / 2"
equation "d1053 = ( ( pod_w / 2 - stack_t ) - lg_gap ) - ( ( pod_w / 2 - stack_t ) - lg_gap - sr_d )"
equation "d1054 = ( ( ( ( pod_d / 2 - wall_depth + cs_front ) + ( ( pod_d / 2 - stack_t ) - ( pod_d / 2 - wall_depth + cs_front ) - lg_l ) / 2 ) + ( ( pod_d / 2 - wall_depth + cs_front ) + ( ( pod_d / 2 - stack_t ) - ( pod_d / 2 - wall_depth + cs_front ) - lg_l ) / 2 ) + lg_l ) / 2 + sr_l / 2 ) - ( ( ( ( pod_d / 2 - wall_depth + cs_front ) + ( ( pod_d / 2 - stack_t ) - ( pod_d / 2 - wall_depth + cs_front ) - lg_l ) / 2 ) + ( ( pod_d / 2 - wall_depth + cs_front ) + ( ( pod_d / 2 - stack_t ) - ( pod_d / 2 - wall_depth + cs_front ) - lg_l ) / 2 ) + lg_l ) / 2 - sr_l / 2 )"
equation "d1055 = abs(( pod_w / 2 - stack_t ) - lg_gap - sr_d)"
equation "d1056 = abs(( ( ( pod_d / 2 - wall_depth + cs_front ) + ( ( pod_d / 2 - stack_t ) - ( pod_d / 2 - wall_depth + cs_front ) - lg_l ) / 2 ) + ( ( pod_d / 2 - wall_depth + cs_front ) + ( ( pod_d / 2 - stack_t ) - ( pod_d / 2 - wall_depth + cs_front ) - lg_l ) / 2 ) + lg_l ) / 2 - sr_l / 2)"
equation "d1057 = ( sr_z + sr_h / 2 ) - ( sr_z - sr_h / 2 )"
equation "d1059 = ( pod_d / 2 - stack_t )"
equation "d1061 = cab_d"
equation "d1062 = abs(feed_x)"
equation "d1063 = abs(cab_z)"
equation "d1064 = -( abs(( ( pod_d / 2 - stack_t ) - sh_t ) - ( ( pod_d / 2 - stack_t ) )) + 1 mm )"
equation "d1066 = ( pod_w / 2 - stack_t )"
equation "d1068 = cab_d"
equation "d1069 = abs(call_y)"
equation "d1070 = abs(cab_z)"
equation "d1071 = -( 2 * sh_t )"
named bodies: "LIGHT SHELF BACK", "LIGHT SHELF LH", "LIGHT SHELF RH", "LED PROFILE RH", "LEDGE TOP", "LEDGE BRACKET 1", "LEDGE BRACKET 2", "SCREEN RAIL"
